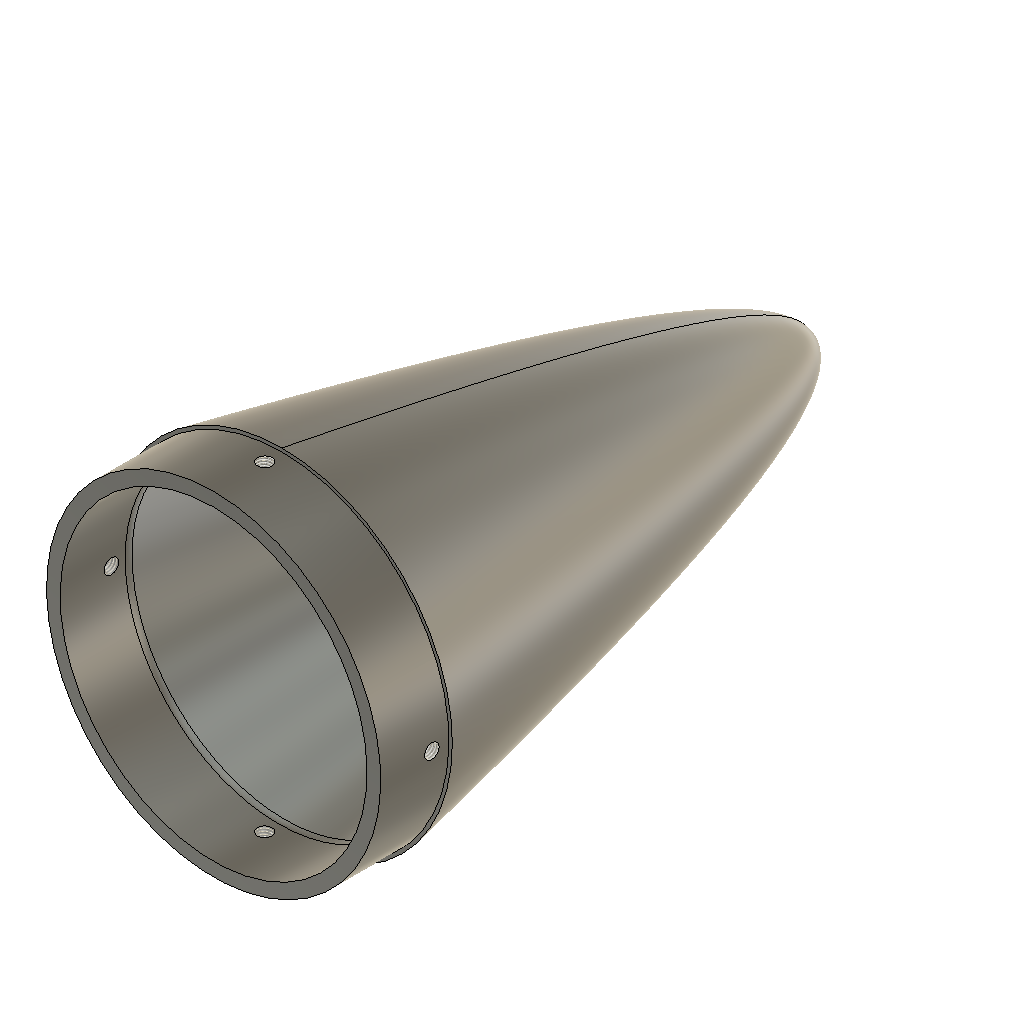
inertia-nosecone-section (Autodesk Fusion 360 design; units mm, degrees)
part number: 2026-10-15-22-11-08-252
Autodesk Fusion 360 part; units mm, degrees
sketch "Sketch1" plane through (0, 0, 0) normal (1, 0, 0) x (0, 1, 0)
  spline S0 degree 5 poles (0, 50) (9.637, 48.0751) (28.5112, 44.2166) (55.6241, 38.4026) (89.2109, 30.5946) (124.8315, 20.6957) (145.0299, 12.5952) (153.1666, 6.3667) (154.9758, 2.1354) (154.9758, 0) knots 0 0 0 0 0 0 0.2 0.4 0.6 0.8 1 1 1 1 1 1
  line L0 (154.9758, 4.1113) -> (154.9758, -4.1113)
  line L1 (149.9758, 0) -> (154.9758, 0)
  spline S1 degree 5 poles (0, 45) (9.3218, 43.2538) (27.5791, 39.7551) (53.8067, 34.4884) (86.2991, 27.426) (120.7646, 18.4984) (140.3171, 11.2264) (148.2042, 5.6627) (149.9682, 1.897) (149.9758, 0) knots 0 0 0 0 0 0 0.2 0.4 0.6 0.8 1 1 1 1 1 1
  line L2 (149.9607, 3.7357) -> (149.9909, -3.7357)
  line L3 (0, 50) -> (0, 45)
  line L4 (-20, 49) -> (-20, 45)
  line L5 (-20, 45) -> (0, 45)
  line L6 (-20, 49) -> (0, 49)
  dimension "d1" = 5
  dimension "d2" = 5
  dimension "d22" = 4
  dimension "d24" = 20
  constraint midpoint S0.end L0
  constraint perpendicular L0 L1
  constraint midpoint L1.start L2
  constraint vertical L3
  constraint perpendicular L3 L5
  constraint coincident L3 L6.end
  constraint perpendicular L3 L6
  measures "d1" distance of S0.start S1.start
  measures "d2" distance of S0.end L1.start
  measures "d22" distance of L4.start L4.end
  measures "d24" distance of L4.start L6.end
revolve "Revolve1" add sketch "Sketch1" angle 360 about axis through (0, 1.75, 0) along (0, 1, 0)
ref_plane "WorkPlane1" through (-49, -9.0426, 0) normal (-1, 0, 0) x (0, 0, -1)
sketch "Sketch3" plane through (-49, 0, 0) normal (-1, 0, 0) x (0, -1, 0)
  point P0 (5, 0)
  dimension "d23" = 5
  measures "d23" distance of origin P0
hole "Hole1" at (-49, -5, 0) direction (1, 0, 0) diameter 4.234 depth 10 tip angle 118
thread "Thread1" "ISO Metric profile 5.0 M5x0.8 M5x0.8 6H" major diameter 5.12 minor diameter 4.234 pitch 0.8 angle 60 resizes the face on face at (-47.6605, -6.975, 0.7622)
pattern_circular "C-Pattern1" count 4 over 360 about axis through (0, 1.75, 0) along (0, 1, 0) of "Hole1"
fillet "Fillet1" radius 10 1 edges at (-41.9547, 0, 16.2727)
